Autodesk Fusion 360 part; units mm, degrees
(part 2 of 2)
sketch "Sketch23" plane through (0, 0, 0) normal (0, 0, 1) x (-1, 0, 0)
  circle A0 centre (51.1884, 99.1347) radius 1.85
  circle A1 centre (75.5913, 102.5343) radius 0.8
  circle A2 centre (-90.0969, -79.2783) radius 0.8
  circle A3 centre (90.1725, -79.2921) radius 0.8
  circle A4 centre (90.1026, 79.3599) radius 0.8
  circle A5 centre (51.1939, -99.1597) radius 1.85
  circle A6 centre (0.0682, 99.4831) radius 1.85
  circle A7 centre (-108.7523, -13.6846) radius 0.8
  circle A8 centre (-51.0571, 99.1371) radius 1.85
  circle A9 centre (75.6553, -102.4768) radius 0.8
  circle A10 centre (108.8477, -13.679) radius 0.8
  circle A11 centre (-89.9874, 79.369) radius 0.8
  circle A12 centre (-51.1366, -99.1566) radius 1.85
  circle A13 centre (108.8477, 13.668) radius 0.8
  circle A14 centre (-75.5979, -102.4631) radius 0.8
  circle A15 centre (-75.515, 102.4682) radius 0.8
  circle A16 centre (-108.7523, 13.7506) radius 0.8
  line L0 (-69.3323, -105.7468) -> (-36.906, -110.0169)
  line L1 (-36.906, -110.0169) -> (36.954, -110.0169)
  line L2 (36.954, -110.0169) -> (69.3862, -105.7589)
  arc A17 (75.995, -107.1982) -> (69.3862, -105.7589) centre (70.688, -115.6738) ccw
  line L3 (75.995, -107.1982) -> (91.7226, -117.0462)
  arc A18 (91.7226, -117.0462) -> (101.3705, -114.8282) centre (95.4376, -111.1132) ccw
  line L4 (101.3705, -114.8282) -> (101.7116, -114.2834)
  line L5 (101.7116, -114.2834) -> (70.2248, -94.5678)
  line L6 (70.2248, -94.5678) -> (80.686, -77.8607)
  line L7 (80.686, -77.8607) -> (112.1728, -97.5763)
  line L8 (112.1728, -97.5763) -> (112.5139, -97.0316)
  arc A19 (112.5139, -97.0316) -> (110.2959, -87.3838) centre (106.581, -93.3167) ccw
  line L9 (110.2959, -87.3838) -> (94.5669, -77.535)
  arc A20 (90.3869, -72.2209) -> (94.5669, -77.535) centre (99.874, -69.0595) ccw
  line L10 (90.3869, -72.2209) -> (80.0477, -41.1942)
  line L11 (80.0477, -41.1942) -> (105.2515, -19.8703)
  arc A21 (111.7105, -17.5046) -> (105.2515, -19.8703) centre (111.7105, -27.5046) ccw
  line L12 (111.7105, -17.5046) -> (130.0589, -17.5046)
  arc A22 (130.0589, -17.5046) -> (137.0576, -10.3672) centre (130.0589, -10.5046) ccw
  line L13 (137.0576, -10.3672) -> (137.0477, -9.8646)
  line L14 (137.0477, -9.8646) -> (100.0477, -9.8646)
  line L15 (100.0477, -9.8646) -> (100.0477, 9.8404)
  line L16 (100.0477, 9.8404) -> (137.0477, 9.8404)
  line L17 (137.0477, 9.8404) -> (137.0579, 10.3626)
  arc A23 (137.0579, 10.3626) -> (130.0593, 17.4996) centre (130.0593, 10.4996) ccw
  line L18 (130.0593, 17.4996) -> (111.707, 17.4996)
  arc A24 (105.2527, 19.8614) -> (111.707, 17.4996) centre (111.707, 27.4996) ccw
  line L19 (105.2527, 19.8614) -> (80.0477, 41.1594)
  line L20 (80.0477, 41.1594) -> (90.3683, 72.2128)
  arc A25 (94.551, 77.5346) -> (90.3683, 72.2128) centre (99.8579, 69.059) ccw
  line L21 (94.551, 77.5346) -> (110.2761, 87.3808)
  arc A26 (110.2761, 87.3808) -> (112.4942, 97.0286) centre (106.5612, 93.3137) ccw
  line L22 (112.4942, 97.0286) -> (112.1557, 97.5692)
  line L23 (112.1557, 97.5692) -> (80.6688, 77.8538)
  line L24 (80.6688, 77.8538) -> (70.2143, 94.5503)
  line L25 (70.2143, 94.5503) -> (101.7012, 114.2657)
  line L26 (101.7012, 114.2657) -> (101.3627, 114.8063)
  arc A27 (101.3627, 114.8063) -> (91.7149, 117.0244) centre (95.4298, 111.0915) ccw
  line L27 (91.7149, 117.0244) -> (75.9857, 107.1756)
  arc A28 (69.38, 105.7359) -> (75.9857, 107.1756) centre (70.6787, 115.6512) ccw
  line L28 (69.38, 105.7359) -> (36.954, 109.9831)
  line L29 (36.954, 109.9831) -> (-0.4655, 114.9106)
  line L30 (-0.4655, 114.9106) -> (-36.8155, 109.9831)
  line L31 (-36.8155, 109.9831) -> (-69.2461, 105.7456)
  arc A29 (-75.8525, 107.1881) -> (-69.2461, 105.7456) centre (-70.5417, 115.6613) ccw
  line L32 (-75.8525, 107.1881) -> (-91.5766, 117.0435)
  arc A30 (-91.5766, 117.0435) -> (-101.2254, 114.8298) centre (-95.2942, 111.1123) ccw
  line L33 (-101.2254, 114.8298) -> (-101.5653, 114.2875)
  line L34 (-101.5653, 114.2875) -> (-70.0873, 94.5579)
  line L35 (-70.0873, 94.5579) -> (-80.5522, 77.8615)
  line L36 (-80.5522, 77.8615) -> (-112.0302, 97.591)
  line L37 (-112.0302, 97.591) -> (-112.3701, 97.0487)
  arc A31 (-112.3701, 97.0487) -> (-110.1564, 87.3999) centre (-106.4389, 93.3312) ccw
  line L38 (-110.1564, 87.3999) -> (-94.4364, 77.547)
  arc A32 (-90.2557, 72.2221) -> (-94.4364, 77.547) centre (-99.7471, 69.0738) ccw
  line L39 (-90.2557, 72.2221) -> (-79.9523, 41.1594)
  line L40 (-79.9523, 41.1594) -> (-105.1606, 19.861)
  arc A33 (-111.6069, 17.4996) -> (-105.1606, 19.861) centre (-111.6145, 27.4996) ccw
  line L41 (-111.6069, 17.4996) -> (-130.1099, 17.4857)
  arc A34 (-130.1099, 17.4857) -> (-137.1046, 10.4595) centre (-130.1047, 10.4857) ccw
  line L42 (-137.1046, 10.4595) -> (-137.1023, 9.8404)
  line L43 (-137.1023, 9.8404) -> (-99.9523, 9.8404)
  line L44 (-99.9523, 9.8404) -> (-99.9523, -9.8646)
  line L45 (-99.9523, -9.8646) -> (-137.1023, -9.8646)
  line L46 (-137.1023, -9.8646) -> (-137.0948, -10.2221)
  arc A35 (-137.0948, -10.2221) -> (-130.1562, -17.0751) centre (-130.0963, -10.0753) ccw
  line L47 (-130.1562, -17.0751) -> (-111.5933, -17.2339)
  arc A36 (-105.1837, -19.63) -> (-111.5933, -17.2339) centre (-111.6789, -27.2335) ccw
  line L48 (-105.1837, -19.63) -> (-79.9523, -41.1835)
  line L49 (-79.9523, -41.1835) -> (-90.3067, -72.2075)
  arc A37 (-94.4901, -77.5202) -> (-90.3067, -72.2075) centre (-99.7924, -69.0416) ccw
  line L50 (-94.4901, -77.5202) -> (-110.2242, -87.3598)
  arc A38 (-110.2242, -87.3598) -> (-112.4476, -97.0064) centre (-106.5126, -93.2948) ccw
  line L51 (-112.4476, -97.0064) -> (-112.1082, -97.549)
  line L52 (-112.1082, -97.549) -> (-80.6103, -77.8512)
  line L53 (-80.6103, -77.8512) -> (-70.1622, -94.5583)
  line L54 (-70.1622, -94.5583) -> (-101.6601, -114.2561)
  line L55 (-101.6601, -114.2561) -> (-101.3208, -114.7987)
  arc A39 (-101.3208, -114.7987) -> (-91.6742, -117.0222) centre (-95.3858, -111.0872) ccw
  line L56 (-91.6742, -117.0222) -> (-75.9402, -107.1826)
  arc A40 (-69.3323, -105.7468) -> (-75.9402, -107.1826) centre (-70.6379, -115.6612) ccw
  line L57 (-0.4655, 114.9106) -> (0.024, -110.0169)
  line L58 (-99.9523, -0.0121) -> (100.0477, -0.0121)
  circle A41 centre (49.1247, -56.1029) radius 1.9
  circle A42 centre (49.1247, -56.1029) radius 4.9
  circle A43 centre (-48.989, 56.0983) radius 1.9
  circle A44 centre (-48.989, 56.0983) radius 4.9
  circle A45 centre (49.1041, 56.0966) radius 1.9
  circle A46 centre (49.1041, 56.0966) radius 4.9
  circle A47 centre (-49.0489, -56.0992) radius 1.9
  circle A48 centre (-49.0489, -56.0992) radius 4.9
  circle A49 centre (49.1247, -56.1029) radius 4.9
  circle A50 centre (-49.0489, -56.0992) radius 4.9
  circle A51 centre (-48.989, 56.0983) radius 4.9
  circle A52 centre (49.1041, 56.0966) radius 4.9
  dimension "d322" = 3.8
  dimension "d323" = 3
  dimension "d325" = 3.8
  dimension "d326" = 3
  dimension "d328" = 3.8
  dimension "d329" = 3
  dimension "d331" = 3.8
  dimension "d332" = 3
  constraint coincident L29.end L30.start
  constraint midpoint L1 L57.end
  constraint midpoint L44 L58.start
  constraint midpoint L15 L58.end
  constraint concentric A41 A49
  constraint concentric A47 A50
  constraint concentric A43 A51
  constraint concentric A45 A52
  measures "d322" diameter of A41
  measures "d325" diameter of A43
  measures "d328" diameter of A45
  measures "d331" diameter of A47
extrude "Extrude34" cut sketch "Sketch23" against normal blind 20 contours A41 | A43 | A45 | A47 bodies 1
sketch "Sketch24" plane through (0, 0, -7) normal (0, 0, -1) x (1, 0, 0)
  circle A0 centre (48.989, 56.0983) radius 1.9
  circle A1 centre (-49.1041, 56.0966) radius 1.9
  circle A2 centre (49.0489, -56.0992) radius 1.9
  circle A3 centre (-49.1247, -56.1029) radius 1.9
  circle A4 centre (-0.0425, -54.0357) radius 4.85
  circle A5 centre (-0.0682, 99.4831) radius 4.85
  line L0 (32.7504, -102.5169) -> (72.4523, -39.0315)
  line L1 (72.4523, -39.0315) -> (72.4523, 39.0033)
  line L2 (72.4523, 39.0033) -> (32.6649, 102.4831)
  line L3 (32.6649, 102.4831) -> (-0.0682, 107.4831)
  line L4 (-0.0682, 107.4831) -> (-32.8012, 102.4831)
  line L5 (-32.8012, 102.4831) -> (-72.5477, 39.0051)
  line L6 (-72.5477, 39.0051) -> (-72.5477, -39.0398)
  line L7 (-72.5477, -39.0398) -> (-32.8013, -102.5169)
  line L8 (-32.8013, -102.5169) -> (32.7504, -102.5169)
  circle A6 centre (-49.1247, -56.1029) radius 3.4
  circle A7 centre (49.0489, -56.0992) radius 3.4
  circle A8 centre (48.989, 56.0983) radius 3.4
  circle A9 centre (-49.1041, 56.0966) radius 3.4
  dimension "d335" = 6.8
  dimension "d336" = 6.8
  dimension "d337" = 6.8
  dimension "d338" = 6.8
  constraint concentric A3 A6
  constraint concentric A2 A7
  constraint concentric A0 A8
  constraint concentric A1 A9
  measures "d335" diameter of A6
  measures "d336" diameter of A7
  measures "d337" diameter of A8
  measures "d338" diameter of A9
extrude "Extrude35" cut sketch "Sketch24" against normal blind 2 contours A6 | A7 | A8 | A9 bodies 1
delete_face "DeleteFace2" 1 faces at (-0.4811, 54.8773, -2) on bodies 1
sketch "Sketch25" plane through (0, 0, 0) normal (0, 0, 1) x (-1, 0, 0)
  line L0 (-69.3323, -105.7468) -> (-36.906, -110.0169)
  line L1 (-36.906, -110.0169) -> (36.954, -110.0169)
  line L2 (36.954, -110.0169) -> (69.3862, -105.7589)
  arc A0 (75.995, -107.1982) -> (69.3862, -105.7589) centre (70.688, -115.6738) ccw
  line L3 (75.995, -107.1982) -> (91.7226, -117.0462)
  arc A1 (91.7226, -117.0462) -> (101.3705, -114.8282) centre (95.4376, -111.1132) ccw
  line L4 (101.3705, -114.8282) -> (101.7116, -114.2834)
  line L5 (101.7116, -114.2834) -> (70.2248, -94.5678)
  line L6 (70.2248, -94.5678) -> (80.686, -77.8607)
  line L7 (80.686, -77.8607) -> (112.1728, -97.5763)
  line L8 (112.1728, -97.5763) -> (112.5139, -97.0316)
  arc A2 (112.5139, -97.0316) -> (110.2959, -87.3838) centre (106.581, -93.3167) ccw
  line L9 (110.2959, -87.3838) -> (94.5669, -77.535)
  arc A3 (90.3869, -72.2209) -> (94.5669, -77.535) centre (99.874, -69.0595) ccw
  line L10 (90.3869, -72.2209) -> (80.0477, -41.1942)
  line L11 (80.0477, -41.1942) -> (105.2515, -19.8703)
  arc A4 (111.7105, -17.5046) -> (105.2515, -19.8703) centre (111.7105, -27.5046) ccw
  line L12 (111.7105, -17.5046) -> (130.0589, -17.5046)
  arc A5 (130.0589, -17.5046) -> (137.0576, -10.3672) centre (130.0589, -10.5046) ccw
  line L13 (137.0576, -10.3672) -> (137.0477, -9.8646)
  line L14 (137.0477, -9.8646) -> (100.0477, -9.8646)
  line L15 (100.0477, -9.8646) -> (100.0477, 9.8404)
  line L16 (100.0477, 9.8404) -> (137.0477, 9.8404)
  line L17 (137.0477, 9.8404) -> (137.0579, 10.3626)
  arc A6 (137.0579, 10.3626) -> (130.0593, 17.4996) centre (130.0593, 10.4996) ccw
  line L18 (130.0593, 17.4996) -> (111.707, 17.4996)
  arc A7 (105.2527, 19.8614) -> (111.707, 17.4996) centre (111.707, 27.4996) ccw
  line L19 (105.2527, 19.8614) -> (80.0477, 41.1594)
  line L20 (80.0477, 41.1594) -> (90.3683, 72.2128)
  arc A8 (94.551, 77.5346) -> (90.3683, 72.2128) centre (99.8579, 69.059) ccw
  line L21 (94.551, 77.5346) -> (110.2761, 87.3808)
  arc A9 (110.2761, 87.3808) -> (112.4942, 97.0286) centre (106.5612, 93.3137) ccw
  line L22 (112.4942, 97.0286) -> (112.1557, 97.5692)
  line L23 (112.1557, 97.5692) -> (80.6688, 77.8538)
  line L24 (80.6688, 77.8538) -> (70.2143, 94.5503)
  line L25 (70.2143, 94.5503) -> (101.7012, 114.2657)
  line L26 (101.7012, 114.2657) -> (101.3627, 114.8063)
  arc A10 (101.3627, 114.8063) -> (91.7149, 117.0244) centre (95.4298, 111.0915) ccw
  line L27 (91.7149, 117.0244) -> (75.9857, 107.1756)
  arc A11 (69.38, 105.7359) -> (75.9857, 107.1756) centre (70.6787, 115.6512) ccw
  line L28 (69.38, 105.7359) -> (36.954, 109.9831)
  line L29 (36.954, 109.9831) -> (-0.4655, 114.9106)
  line L30 (-0.4655, 114.9106) -> (-36.8155, 109.9831)
  line L31 (-36.8155, 109.9831) -> (-69.2461, 105.7456)
  arc A12 (-75.8525, 107.1881) -> (-69.2461, 105.7456) centre (-70.5417, 115.6613) ccw
  line L32 (-75.8525, 107.1881) -> (-91.5766, 117.0435)
  arc A13 (-91.5766, 117.0435) -> (-101.2254, 114.8298) centre (-95.2942, 111.1123) ccw
  line L33 (-101.2254, 114.8298) -> (-101.5653, 114.2875)
  line L34 (-101.5653, 114.2875) -> (-70.0873, 94.5579)
  line L35 (-70.0873, 94.5579) -> (-80.5522, 77.8615)
  line L36 (-80.5522, 77.8615) -> (-112.0302, 97.591)
  line L37 (-112.0302, 97.591) -> (-112.3701, 97.0487)
  arc A14 (-112.3701, 97.0487) -> (-110.1564, 87.3999) centre (-106.4389, 93.3312) ccw
  line L38 (-110.1564, 87.3999) -> (-94.4364, 77.547)
  arc A15 (-90.2557, 72.2221) -> (-94.4364, 77.547) centre (-99.7471, 69.0738) ccw
  line L39 (-90.2557, 72.2221) -> (-79.9523, 41.1594)
  line L40 (-79.9523, 41.1594) -> (-105.1606, 19.861)
  arc A16 (-111.6069, 17.4996) -> (-105.1606, 19.861) centre (-111.6145, 27.4996) ccw
  line L41 (-111.6069, 17.4996) -> (-130.1099, 17.4857)
  arc A17 (-130.1099, 17.4857) -> (-137.1046, 10.4595) centre (-130.1047, 10.4857) ccw
  line L42 (-137.1046, 10.4595) -> (-137.1023, 9.8404)
  line L43 (-137.1023, 9.8404) -> (-99.9523, 9.8404)
  line L44 (-99.9523, 9.8404) -> (-99.9523, -9.8646)
  line L45 (-99.9523, -9.8646) -> (-137.1023, -9.8646)
  line L46 (-137.1023, -9.8646) -> (-137.0948, -10.2221)
  arc A18 (-137.0948, -10.2221) -> (-130.1562, -17.0751) centre (-130.0963, -10.0753) ccw
  line L47 (-130.1562, -17.0751) -> (-111.5933, -17.2339)
  arc A19 (-105.1837, -19.63) -> (-111.5933, -17.2339) centre (-111.6789, -27.2335) ccw
  line L48 (-105.1837, -19.63) -> (-79.9523, -41.1835)
  line L49 (-79.9523, -41.1835) -> (-90.3067, -72.2075)
  arc A20 (-94.4901, -77.5202) -> (-90.3067, -72.2075) centre (-99.7924, -69.0416) ccw
  line L50 (-94.4901, -77.5202) -> (-110.2242, -87.3598)
  arc A21 (-110.2242, -87.3598) -> (-112.4476, -97.0064) centre (-106.5126, -93.2948) ccw
  line L51 (-112.4476, -97.0064) -> (-112.1082, -97.549)
  line L52 (-112.1082, -97.549) -> (-80.6103, -77.8512)
  line L53 (-80.6103, -77.8512) -> (-70.1622, -94.5583)
  line L54 (-70.1622, -94.5583) -> (-101.6601, -114.2561)
  line L55 (-101.6601, -114.2561) -> (-101.3208, -114.7987)
  arc A22 (-101.3208, -114.7987) -> (-91.6742, -117.0222) centre (-95.3858, -111.0872) ccw
  line L56 (-91.6742, -117.0222) -> (-75.9402, -107.1826)
  arc A23 (-69.3323, -105.7468) -> (-75.9402, -107.1826) centre (-70.6379, -115.6612) ccw
  circle A24 centre (-108.7523, 13.7506) radius 0.8
  circle A25 centre (-75.515, 102.4682) radius 0.8
  circle A26 centre (-75.5979, -102.4631) radius 0.8
  circle A27 centre (108.8477, 13.668) radius 0.8
  circle A28 centre (-51.1366, -99.1566) radius 1.85
  circle A29 centre (-89.9874, 79.369) radius 0.8
  circle A30 centre (108.8477, -13.679) radius 0.8
  circle A31 centre (75.6553, -102.4768) radius 0.8
  circle A32 centre (-51.0571, 99.1371) radius 1.85
  circle A33 centre (-108.7523, -13.6846) radius 0.8
  circle A34 centre (0.0682, 99.4831) radius 1.85
  circle A35 centre (51.1939, -99.1597) radius 1.85
  circle A36 centre (90.1026, 79.3599) radius 0.8
  circle A37 centre (90.1725, -79.2921) radius 0.8
  circle A38 centre (-90.0969, -79.2783) radius 0.8
  circle A39 centre (75.5913, 102.5343) radius 0.8
  circle A40 centre (51.1884, 99.1347) radius 1.85
  circle A41 centre (49.1247, -56.1029) radius 1.9
  circle A42 centre (-49.0489, -56.0992) radius 1.9
  circle A43 centre (49.1041, 56.0966) radius 1.9
  circle A44 centre (-48.989, 56.0983) radius 1.9
  circle A45 centre (0.0425, -54.0357) radius 1.85
  line L57 (-12.5, 5) -> (12.5, 5)
  line L58 (12.5, 5) -> (12.5, -5)
  line L59 (12.5, -5) -> (-12.5, -5)
  line L60 (-12.5, -5) -> (-12.5, 5)
  line L61 (-12.5, 5) -> (12.5, -5) construction
  line L62 (12.5, 5) -> (-12.5, -5) construction
  dimension "d341" = 25
  dimension "d342" = 10
  constraint horizontal L57
  constraint perpendicular L57 L58
  constraint parallel L57 L59
  constraint parallel L58 L60
  constraint coincident L61 origin
  constraint coincident L62 origin
  measures "d341" distance of L58.end L59.end
  measures "d342" distance of L57.end L58.end
extrude "Extrude36" cut sketch "Sketch25" against normal blind 40 contours L57 L58 L59 L60 bodies 1
chamfer "Chamfer10" distance 5 angle 45 4 edges at (0, 5, 0) (-12.5, 0, 0) (12.5, 0, 0) (0, -5, 0) on bodies 1
extrude "Extrude37" add 1 faces at (-52.5318, 1.6782, -7) along direction (0, 0, -1) blind 0.9 on bodies 1 bodies 1
sketch "Sketch26" plane through (0, 0, 0) normal (0, 0, 1) x (-1, 0, 0)
  circle A0 centre (0.0425, -54.0357) radius 1.85
  circle A1 centre (-48.989, 56.0983) radius 1.9
  circle A2 centre (49.1041, 56.0966) radius 1.9
  circle A3 centre (-49.0489, -56.0992) radius 1.9
  circle A4 centre (49.1247, -56.1029) radius 1.9
  circle A5 centre (51.1884, 99.1347) radius 1.85
  circle A6 centre (75.5913, 102.5343) radius 0.8
  circle A7 centre (-90.0969, -79.2783) radius 0.8
  circle A8 centre (90.1725, -79.2921) radius 0.8
  circle A9 centre (90.1026, 79.3599) radius 0.8
  circle A10 centre (51.1939, -99.1597) radius 1.85
  circle A11 centre (0.0682, 99.4831) radius 1.85
  circle A12 centre (-108.7523, -13.6846) radius 0.8
  circle A13 centre (-51.0571, 99.1371) radius 1.85
  circle A14 centre (75.6553, -102.4768) radius 0.8
  circle A15 centre (108.8477, -13.679) radius 0.8
  circle A16 centre (-89.9874, 79.369) radius 0.8
  circle A17 centre (-51.1366, -99.1566) radius 1.85
  circle A18 centre (108.8477, 13.668) radius 0.8
  circle A19 centre (-75.5979, -102.4631) radius 0.8
  circle A20 centre (-75.515, 102.4682) radius 0.8
  circle A21 centre (-108.7523, 13.7506) radius 0.8
  line L0 (-69.3323, -105.7468) -> (-36.906, -110.0169)
  line L1 (-36.906, -110.0169) -> (36.954, -110.0169)
  line L2 (36.954, -110.0169) -> (69.3862, -105.7589)
  arc A22 (75.995, -107.1982) -> (69.3862, -105.7589) centre (70.688, -115.6738) ccw
  line L3 (75.995, -107.1982) -> (91.7226, -117.0462)
  arc A23 (91.7226, -117.0462) -> (101.3705, -114.8282) centre (95.4376, -111.1132) ccw
  line L4 (101.3705, -114.8282) -> (101.7116, -114.2834)
  line L5 (101.7116, -114.2834) -> (70.2248, -94.5678)
  line L6 (70.2248, -94.5678) -> (80.686, -77.8607)
  line L7 (80.686, -77.8607) -> (112.1728, -97.5763)
  line L8 (112.1728, -97.5763) -> (112.5139, -97.0316)
  arc A24 (112.5139, -97.0316) -> (110.2959, -87.3838) centre (106.581, -93.3167) ccw
  line L9 (110.2959, -87.3838) -> (94.5669, -77.535)
  arc A25 (90.3869, -72.2209) -> (94.5669, -77.535) centre (99.874, -69.0595) ccw
  line L10 (90.3869, -72.2209) -> (80.0477, -41.1942)
  line L11 (80.0477, -41.1942) -> (105.2515, -19.8703)
  arc A26 (111.7105, -17.5046) -> (105.2515, -19.8703) centre (111.7105, -27.5046) ccw
  line L12 (111.7105, -17.5046) -> (130.0589, -17.5046)
  arc A27 (130.0589, -17.5046) -> (137.0576, -10.3672) centre (130.0589, -10.5046) ccw
  line L13 (137.0576, -10.3672) -> (137.0477, -9.8646)
  line L14 (137.0477, -9.8646) -> (100.0477, -9.8646)
  line L15 (100.0477, -9.8646) -> (100.0477, 9.8404)
  line L16 (100.0477, 9.8404) -> (137.0477, 9.8404)
  line L17 (137.0477, 9.8404) -> (137.0579, 10.3626)
  arc A28 (137.0579, 10.3626) -> (130.0593, 17.4996) centre (130.0593, 10.4996) ccw
  line L18 (130.0593, 17.4996) -> (111.707, 17.4996)
  arc A29 (105.2527, 19.8614) -> (111.707, 17.4996) centre (111.707, 27.4996) ccw
  line L19 (105.2527, 19.8614) -> (80.0477, 41.1594)
  line L20 (80.0477, 41.1594) -> (90.3683, 72.2128)
  arc A30 (94.551, 77.5346) -> (90.3683, 72.2128) centre (99.8579, 69.059) ccw
  line L21 (94.551, 77.5346) -> (110.2761, 87.3808)
  arc A31 (110.2761, 87.3808) -> (112.4942, 97.0286) centre (106.5612, 93.3137) ccw
  line L22 (112.4942, 97.0286) -> (112.1557, 97.5692)
  line L23 (112.1557, 97.5692) -> (80.6688, 77.8538)
  line L24 (80.6688, 77.8538) -> (70.2143, 94.5503)
  line L25 (70.2143, 94.5503) -> (101.7012, 114.2657)
  line L26 (101.7012, 114.2657) -> (101.3627, 114.8063)
  arc A32 (101.3627, 114.8063) -> (91.7149, 117.0244) centre (95.4298, 111.0915) ccw
  line L27 (91.7149, 117.0244) -> (75.9857, 107.1756)
  arc A33 (69.38, 105.7359) -> (75.9857, 107.1756) centre (70.6787, 115.6512) ccw
  line L28 (69.38, 105.7359) -> (36.954, 109.9831)
  line L29 (36.954, 109.9831) -> (-0.4655, 114.9106)
  line L30 (-0.4655, 114.9106) -> (-36.8155, 109.9831)
  line L31 (-36.8155, 109.9831) -> (-69.2461, 105.7456)
  arc A34 (-75.8525, 107.1881) -> (-69.2461, 105.7456) centre (-70.5417, 115.6613) ccw
  line L32 (-75.8525, 107.1881) -> (-91.5766, 117.0435)
  arc A35 (-91.5766, 117.0435) -> (-101.2254, 114.8298) centre (-95.2942, 111.1123) ccw
  line L33 (-101.2254, 114.8298) -> (-101.5653, 114.2875)
  line L34 (-101.5653, 114.2875) -> (-70.0873, 94.5579)
  line L35 (-70.0873, 94.5579) -> (-80.5522, 77.8615)
  line L36 (-80.5522, 77.8615) -> (-112.0302, 97.591)
  line L37 (-112.0302, 97.591) -> (-112.3701, 97.0487)
  arc A36 (-112.3701, 97.0487) -> (-110.1564, 87.3999) centre (-106.4389, 93.3312) ccw
  line L38 (-110.1564, 87.3999) -> (-94.4364, 77.547)
  arc A37 (-90.2557, 72.2221) -> (-94.4364, 77.547) centre (-99.7471, 69.0738) ccw
  line L39 (-90.2557, 72.2221) -> (-79.9523, 41.1594)
  line L40 (-79.9523, 41.1594) -> (-105.1606, 19.861)
  arc A38 (-111.6069, 17.4996) -> (-105.1606, 19.861) centre (-111.6145, 27.4996) ccw
  line L41 (-111.6069, 17.4996) -> (-130.1099, 17.4857)
  arc A39 (-130.1099, 17.4857) -> (-137.1046, 10.4595) centre (-130.1047, 10.4857) ccw
  line L42 (-137.1046, 10.4595) -> (-137.1023, 9.8404)
  line L43 (-137.1023, 9.8404) -> (-99.9523, 9.8404)
  line L44 (-99.9523, 9.8404) -> (-99.9523, -9.8646)
  line L45 (-99.9523, -9.8646) -> (-137.1023, -9.8646)
  line L46 (-137.1023, -9.8646) -> (-137.0948, -10.2221)
  arc A40 (-137.0948, -10.2221) -> (-130.1562, -17.0751) centre (-130.0963, -10.0753) ccw
  line L47 (-130.1562, -17.0751) -> (-111.5933, -17.2339)
  arc A41 (-105.1837, -19.63) -> (-111.5933, -17.2339) centre (-111.6789, -27.2335) ccw
  line L48 (-105.1837, -19.63) -> (-79.9523, -41.1835)
  line L49 (-79.9523, -41.1835) -> (-90.3067, -72.2075)
  arc A42 (-94.4901, -77.5202) -> (-90.3067, -72.2075) centre (-99.7924, -69.0416) ccw
  line L50 (-94.4901, -77.5202) -> (-110.2242, -87.3598)
  arc A43 (-110.2242, -87.3598) -> (-112.4476, -97.0064) centre (-106.5126, -93.2948) ccw
  line L51 (-112.4476, -97.0064) -> (-112.1082, -97.549)
  line L52 (-112.1082, -97.549) -> (-80.6103, -77.8512)
  line L53 (-80.6103, -77.8512) -> (-70.1622, -94.5583)
  line L54 (-70.1622, -94.5583) -> (-101.6601, -114.2561)
  line L55 (-101.6601, -114.2561) -> (-101.3208, -114.7987)
  arc A44 (-101.3208, -114.7987) -> (-91.6742, -117.0222) centre (-95.3858, -111.0872) ccw
  line L56 (-91.6742, -117.0222) -> (-75.9402, -107.1826)
  arc A45 (-69.3323, -105.7468) -> (-75.9402, -107.1826) centre (-70.6379, -115.6612) ccw
  line L57 (-17.5, 10) -> (17.5, 10)
  line L58 (17.5, 10) -> (17.5, -10)
  line L59 (17.5, -10) -> (-17.5, -10)
  line L60 (-17.5, -10) -> (-17.5, 10)
  line L61 (-80.6103, -77.8512) -> (-88.1607, -65.7777)
  line L62 (-88.1607, -65.7777) -> (-79.9523, -41.1835)
  line L63 (-99.9523, -9.8646) -> (-99.9523, -24.0989)
  line L64 (-99.9523, -24.0989) -> (-79.9523, -41.1835)
  line L65 (-99.9523, 9.8404) -> (-99.9523, 24.2615)
  line L66 (-99.9523, 24.2615) -> (-79.9523, 41.1594)
  line L67 (-80.5522, 77.8615) -> (-88.1208, 65.7859)
  line L68 (-88.1208, 65.7859) -> (-79.9523, 41.1594)
  line L69 (-80.5522, 77.8615) -> (-62.5247, 106.6238)
  line L70 (-99.9523, -9.8646) -> (-99.9523, 9.8404)
  line L71 (-80.6103, -77.8512) -> (-62.6118, -106.6318)
  line L72 (-62.5247, 106.6238) -> (-0.4655, 114.9106)
  line L73 (70.2143, 94.5503) -> (62.6593, 106.6162)
  line L74 (62.6593, 106.6162) -> (-1.2851, 115.0366)
  line L75 (70.2143, 94.5503) -> (88.2298, 65.7783)
  line L76 (88.2298, 65.7783) -> (80.0477, 41.1594)
  line L77 (100.0477, 9.8404) -> (100.0477, 24.2596)
  line L78 (100.0477, 24.2596) -> (80.0477, 41.1594)
  line L79 (100.0477, 9.8404) -> (100.0477, -24.273)
  line L80 (100.0477, -24.273) -> (80.0477, -41.1942)
  line L81 (80.686, -77.8607) -> (88.244, -65.7903)
  line L82 (80.0477, -41.1942) -> (88.244, -65.7903)
  line L83 (80.686, -77.8607) -> (62.6649, -106.6413)
  line L84 (62.6649, -106.6413) -> (36.954, -110.0169)
  line L85 (36.954, -110.0169) -> (-36.906, -110.0169)
  line L86 (-62.6118, -106.6318) -> (-36.906, -110.0169)
  line L87 (-59.5353, 101.9786) -> (-0.3928, 109.8759)
  line L88 (-76.3156, 75.2061) -> (-59.5353, 101.9786)
  line L89 (-76.3156, 75.2061) -> (-82.6338, 65.1254)
  line L90 (-82.6338, 65.1254) -> (-74.1416, 39.5231)
  line L91 (-94.9523, 21.9403) -> (-74.1416, 39.5231)
  line L92 (-94.9523, 9.8404) -> (-94.9523, 21.9403)
  line L93 (-94.9523, -9.8646) -> (-94.9523, 9.8404)
  line L94 (-94.9523, -9.8646) -> (-94.9523, -21.7941)
  line L95 (-94.9523, -21.7941) -> (-74.1427, -39.5703)
  line L96 (-82.6717, -65.1249) -> (-74.1427, -39.5703)
  line L97 (-76.371, -75.2) -> (-82.6717, -65.1249)
  line L98 (-76.371, -75.2) -> (-59.6222, -101.9823)
  line L99 (-59.6222, -101.9823) -> (-36.5782, -105.0169)
  line L100 (36.6272, -105.0169) -> (-36.5782, -105.0169)
  line L101 (59.6777, -101.9906) -> (36.6272, -105.0169)
  line L102 (76.4482, -75.2072) -> (59.6777, -101.9906)
  line L103 (76.4482, -75.2072) -> (82.7552, -65.1347)
  line L104 (74.234, -39.5635) -> (82.7552, -65.1347)
  line L105 (95.0477, -21.9539) -> (74.234, -39.5635)
  line L106 (95.0477, 9.8404) -> (95.0477, -21.9539)
  line L107 (95.0477, 9.8404) -> (95.0477, 21.9385)
  line L108 (95.0477, 21.9385) -> (74.2355, 39.5247)
  line L109 (82.7423, 65.1206) -> (74.2355, 39.5247)
  line L110 (65.9765, 91.8968) -> (82.7423, 65.1206)
  line L111 (65.9765, 91.8968) -> (59.6714, 101.9665)
  line L112 (59.6714, 101.9665) -> (-0.3928, 109.8759)
  circle A46 centre (74.7552, -65.1347) radius 4
  circle A47 centre (74.7552, -65.1347) radius 1.9
  line L113 (-82.6717, -65.1249) -> (-74.6717, -65.1249)
  circle A48 centre (-74.6717, -65.1249) radius 4
  circle A49 centre (-74.6717, -65.1249) radius 1.9
  line L114 (82.7423, 65.1206) -> (74.7423, 65.1206)
  circle A50 centre (74.7423, 65.1206) radius 4
  circle A51 centre (74.7423, 65.1206) radius 1.9
  line L115 (-82.6338, 65.1254) -> (-74.6338, 65.1254)
  circle A52 centre (-74.6338, 65.1254) radius 4
  circle A53 centre (-74.6338, 65.1254) radius 1.9
  dimension "d348" = 5
  dimension "d351" = 8
  dimension "d352" = 8
  dimension "d353" = 3.8
  dimension "d354" = 8
  dimension "d355" = 8
  dimension "d356" = 3.8
  dimension "d357" = 8
  dimension "d358" = 8
  dimension "d359" = 3.8
  dimension "d360" = 8
  dimension "d361" = 8
  dimension "d362" = 3.8
  constraint coincident L52.end L53.start
  constraint coincident L49 L61.end
  constraint perpendicular L52 L61
  constraint coincident L48.end L49.start
  constraint coincident L44.end L45.start
  constraint coincident L48 L63.end
  constraint perpendicular L45 L63
  constraint coincident L43.end L44.start
  constraint coincident L40 L65.end
  constraint perpendicular L43 L65
  constraint coincident L39.end L40.start
  constraint coincident L35.end L36.start
  constraint coincident L39 L67.end
  constraint perpendicular L36 L67
  constraint coincident L31 L69.end
  constraint perpendicular L34 L69
  constraint coincident L0 L71.end
  constraint perpendicular L54 L71
  constraint coincident L29.end L30.start
  constraint coincident L24.end L25.start
  constraint coincident L28 L73.end
  constraint perpendicular L25 L73
  constraint parallel L29 L74
  constraint coincident L20 L75.end
  constraint perpendicular L23 L75
  constraint coincident L19.end L20.start
  constraint coincident L15.end L16.start
  constraint coincident L19 L77.end
  constraint perpendicular L16 L77
  constraint coincident L11 L79.end
  constraint parallel L15 L79
  constraint coincident L10.end L11.start
  constraint coincident L6.end L7.start
  constraint coincident L10 L81.end
  constraint perpendicular L7 L81
  constraint coincident L2 L83.end
  constraint perpendicular L5 L83
  constraint coincident L1.end L2.start
  constraint coincident L0.end L1.start
  constraint concentric A46 A47
  constraint horizontal L113
  constraint coincident L113.end A48.centre
  constraint concentric A48 A49
  constraint horizontal L114
  constraint coincident L114.end A50.centre
  constraint concentric A50 A51
  constraint horizontal L115
  constraint coincident L115.end A52.centre
  constraint concentric A52 A53
  measures "d351" distance of L103.end A46.centre
  measures "d352" diameter of A46
  measures "d353" diameter of A47
  measures "d354" distance of L96.start L113.end
  measures "d355" diameter of A48
  measures "d356" diameter of A49
  measures "d357" distance of L109.start L114.end
  measures "d358" diameter of A50
  measures "d359" diameter of A51
  measures "d360" distance of L89.end L115.end
  measures "d361" diameter of A52
  measures "d362" diameter of A53
extrude "Extrude38" add sketch "Sketch26" along normal blind 18 contours L0 L1 L2 L6 L10 L11 L15 L19 L20 L24 L28 L29 L30 L31 L35 L39 L40 L44 L48 L49 L53 L61 L62 L63 L64 L65 L66 L67 L68 L69 L70 L71 L73 L75 L76 L77 L78 L79 L80 L81 L82 L83 L84 L85 L86 bodies 1
extrude "Extrude39" add sketch "Sketch26" along normal blind 18 contours A46 | A48 | A50 | A52 bodies 1
delete_face "DeleteFace3" 1 faces at (-4.9122, -99.7248, -8.5667) on bodies 1
delete_face "DeleteFace4" 1 faces at (-4.8864, 53.7939, -8.5667) on bodies 1

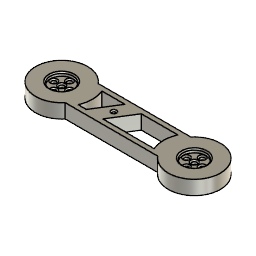
design "FemurHornSideV2"
part number: 2025-10-31-15-56-20-777
Autodesk Fusion 360 part; units mm, degrees
sketch "Sketch1" plane through (0, 0, 0) normal (0, 0, 1) x (1, 0, 0)
  line L0 (39.0943, -14) -> (-39.0943, -14)
  line L1 (-39.0943, 14) -> (39.0943, 14)
  line L2 (35.2103, -7.0421) -> (-35.2103, 7.0421) construction
  line L3 (-35.2103, -7.0421) -> (35.2103, 7.0421) construction
  circle A0 centre (56, 0) radius 21.95
  circle A1 centre (-56, 0) radius 21.95
  circle A2 centre (56, 0) radius 13
  line L4 (-39.0943, -14) -> (-24.0943, -14)
  line L5 (-21.5994, -10) -> (-9.1249, 10)
  line L6 (-6.6301, 14) -> (0.1699, 14)
  line L7 (-2.3249, 10) -> (-14.7994, -10)
  line L8 (-24.0943, -14) -> (-17.2943, -14)
  line L9 (1.2108, 10) -> (-11.2637, -10)
  line L10 (-25.1351, -10) -> (-12.6607, 10)
  line L11 (-24.0943, -14) -> (-17.2943, -14)
  line L12 (-2.3249, 10) -> (-14.7994, -10)
  line L13 (-6.6301, 14) -> (0.1699, 14)
  line L14 (-21.5994, -10) -> (-9.1249, 10)
  arc A3 (-32.0542, -10) -> (-32.0542, 10) centre (-56, 0) ccw
  line L15 (32.0542, -10) -> (-32.0542, -10)
  line L16 (-32.0542, 10) -> (32.0542, 10)
  arc A4 (32.0542, 10) -> (32.0542, -10) centre (56, 0) ccw
  circle A5 centre (-56, 0) radius 2
  circle A6 centre (-56, 0) radius 19.95
  circle A7 centre (-56, 0) radius 13.34
  circle A8 centre (-56, 0) radius 9.65
  circle A9 centre (-56, 6.65) radius 3
  circle A10 centre (-56, 6.65) radius 1.9
  circle A11 centre (-62.65, 0) radius 1.9
  circle A12 centre (-56, -6.65) radius 1.9
  circle A13 centre (-49.35, 0) radius 1.9
  circle A14 centre (56, 0) radius 2
  circle A15 centre (56, 0) radius 19.95
  circle A16 centre (56, 0) radius 9.65
  circle A17 centre (49.35, 0.0073) radius 3
  circle A18 centre (49.35, 0.0073) radius 1.9
  circle A19 centre (55.9927, -6.65) radius 1.9
  circle A20 centre (62.65, -0.0073) radius 1.9
  circle A21 centre (56.0073, 6.65) radius 1.9
  line L17 (-9.1249, 10) -> (-2.3249, 10)
  dimension "d11" = 26
  dimension "d15" = 15
  dimension "d16" = 33
  dimension "d32" = 4
  dimension "d43" = 3.8
  dimension "d45" = 360
  dimension "d51" = 4
  dimension "d53" = 19.3
  dimension "d55" = 6
  dimension "d56" = 3.8
  dimension "d58" = 360
  dimension "d95" = 6.8
  dimension "d96" = 78.1886
  dimension "d97" = 39.9
  dimension "d98" = 43.9
  dimension "d99" = 64.1084
  constraint horizontal L0
  constraint parallel L0 L1
  constraint coincident L2 origin
  constraint coincident L3 origin
  constraint coincident A1 L1.start
  constraint coincident A1 L0.end
  constraint coincident A1 L3.start
  constraint coincident A1 L2.end
  constraint coincident A0 L1.end
  constraint coincident A0 L0.start
  constraint coincident A0 L3.end
  constraint coincident A0 L2.start
  constraint parallel L0 L4
  constraint coincident L1 L6.start
  constraint parallel L1 L6
  constraint coincident L0 L8.end
  constraint concentric A1 A3
  constraint coincident L15 L10.start
  constraint coincident L15 L7.end
  constraint coincident L15 L5.start
  constraint coincident L15 L9.end
  constraint concentric A0 A4
  constraint coincident L16 L10.end
  constraint coincident L16 L5.end
  constraint coincident L16 L7.start
  constraint coincident L16 L9.start
  constraint concentric A3 A6
  constraint concentric A5 A7
  constraint concentric A6 A8
  constraint concentric A9 A10
  constraint concentric A2 A14
  constraint concentric A0 A15
  constraint concentric A0 A16
  constraint concentric A17 A18
  measures "d11" diameter of A2
  measures "d15" distance of L0.end L4.end
  measures "d16" distance of L4.end L6.start
  measures "d32" diameter of A5
  measures "d43" diameter of A10
  measures "d51" diameter of A14
  measures "d53" diameter of A16
  measures "d55" diameter of A17
  measures "d56" diameter of A18
  measures "d95" distance of L5.end L7.start
  measures "d96" distance of L1.start L1.end
  measures "d97" diameter of A15
  measures "d98" diameter of A0
  measures "d99" distance of A3.end L16.end
extrude "Extrude1" add sketch "Sketch1" along normal blind 12 contours L0 L1 A0 A1 L4 L6 L8 L11 L13 | A0 | A1 | A2 | L5 L10 L14 L15 L16 | L7 L9 L12 L15 L16 | A5 | A6 | A7 | A9 | A8 | A10 | A11 | A12 | A13 | A14 | A15 | A17 | A16 | A18 | A19 | A20 | A21
extrude "Extrude4" cut sketch "Sketch1" along normal blind 17 contours A5
extrude "Extrude5" cut sketch "Sketch1" along normal blind 17 contours A10 | A11 | A12 | A13
extrude "Extrude7" cut sketch "Sketch1" along normal blind 12 contours A14 | A18 | A19 | A20 | A21
sketch "Sketch8" plane through (0, 0, 0) normal (0, 0, -1) x (1, 0, 0)
  circle A0 centre (55.9927, 6.65) radius 1.9
  circle A1 centre (49.35, -0.0073) radius 1.9
  circle A2 centre (62.65, 0.0073) radius 1.9
  circle A3 centre (56, 0) radius 2
  circle A4 centre (56.0073, -6.65) radius 1.9
  circle A5 centre (-56, 6.65) radius 1.9
  circle A6 centre (-62.65, 0) radius 1.9
  circle A7 centre (-49.35, 0) radius 1.9
  circle A8 centre (-56, -6.65) radius 1.9
  circle A9 centre (-56, 0) radius 2
  line L0 (-25.1351, 10) -> (-12.6607, -10)
  line L1 (-12.6607, -10) -> (-32.0542, -10)
  arc A10 (-32.0542, -10) -> (-32.0542, 10) centre (-56, 0) ccw
  line L2 (-32.0542, 10) -> (-25.1351, 10)
  line L3 (-21.5994, 10) -> (-14.7994, 10)
  line L4 (-14.7994, 10) -> (-2.3249, -10)
  line L5 (-2.3249, -10) -> (-9.1249, -10)
  line L6 (-9.1249, -10) -> (-21.5994, 10)
  line L7 (1.2108, -10) -> (-11.2637, 10)
  line L8 (-11.2637, 10) -> (32.0542, 10)
  arc A11 (32.0542, 10) -> (32.0542, -10) centre (56, 0) ccw
  line L9 (32.0542, -10) -> (1.2108, -10)
  arc A12 (-39.0943, 14) -> (-39.0943, -14) centre (-56, 0) ccw
  line L10 (-39.0943, -14) -> (39.0943, -14)
  arc A13 (39.0943, -14) -> (39.0943, 14) centre (56, 0) ccw
  line L11 (39.0943, 14) -> (-39.0943, 14)
  circle A14 centre (-56, 0) radius 10
  circle A15 centre (56, 0) radius 10
  dimension "d81" = 20
  dimension "d82" = 20
  constraint concentric A9 A14
  constraint concentric A3 A15
  measures "d81" diameter of A14
  measures "d82" diameter of A15
extrude "Extrude13" cut sketch "Sketch8" against normal blind 6 contours A14 | A15
sketch "Sketch9" plane through (0, 0, 12) normal (0, 0, 1) x (-1, 0, 0)
  line L0 (12.6607, -10) -> (25.1351, 10)
  line L1 (25.1351, 10) -> (32.0542, 10)
  arc A0 (32.0542, 10) -> (32.0542, -10) centre (56, 0) ccw
  line L2 (32.0542, -10) -> (12.6607, -10)
  line L3 (14.7994, 10) -> (21.5994, 10)
  line L4 (21.5994, 10) -> (9.1249, -10)
  line L5 (9.1249, -10) -> (2.3249, -10)
  line L6 (2.3249, -10) -> (14.7994, 10)
  line L7 (11.2637, 10) -> (-1.2108, -10)
  line L8 (-1.2108, -10) -> (-32.0542, -10)
  arc A1 (-32.0542, -10) -> (-32.0542, 10) centre (-56, 0) ccw
  line L9 (-32.0542, 10) -> (11.2637, 10)
  arc A2 (39.0943, -14) -> (39.0943, 14) centre (56, 0) ccw
  line L10 (39.0943, 14) -> (-39.0943, 14)
  arc A3 (-39.0943, 14) -> (-39.0943, -14) centre (-56, 0) ccw
  line L11 (-39.0943, -14) -> (39.0943, -14)
  line L12 (21.445, 9.2275) -> (8.9704, -10.7727)
  line L13 (8.9704, -10.7727) -> (2.17, -10.7727)
  line L14 (21.445, 9.2275) -> (14.645, 9.2275)
  line L15 (14.645, 9.2275) -> (2.17, -10.7727)
  circle A4 centre (-55.9927, 6.65) radius 1.9
  circle A5 centre (-49.35, -0.0073) radius 1.9
  circle A6 centre (-62.65, 0.0073) radius 1.9
  circle A7 centre (-56, 0) radius 2
  circle A8 centre (-56.0073, -6.65) radius 1.9
  circle A9 centre (56, 6.65) radius 1.9
  circle A10 centre (62.65, 0) radius 1.9
  circle A11 centre (49.35, 0) radius 1.9
  circle A12 centre (56, -6.65) radius 1.9
  circle A13 centre (56, 0) radius 2
  constraint parallel L4 L12
  constraint parallel L5 L13
  constraint parallel L3 L14
extrude "Extrude14" add sketch "Sketch9" against normal blind 7 contours L3 L4 L5 L6 L14 L15 | L4 L5 L14 L15
sketch "Sketch10" plane through (0, 0, 12) normal (0, 0, 1) x (-1, 0, 0)
  line L0 (12.6607, -10) -> (25.1351, 10)
  line L1 (25.1351, 10) -> (32.0542, 10)
  arc A0 (32.0542, 10) -> (32.0542, -10) centre (56, 0) ccw
  line L2 (32.0542, -10) -> (12.6607, -10)
  line L3 (11.2637, 10) -> (-1.2108, -10)
  line L4 (-1.2108, -10) -> (-32.0542, -10)
  arc A1 (-32.0542, -10) -> (-32.0542, 10) centre (-56, 0) ccw
  line L5 (-32.0542, 10) -> (11.2637, 10)
  arc A2 (39.0943, -14) -> (39.0943, 14) centre (56, 0) ccw
  line L6 (39.0943, 14) -> (-39.0943, 14)
  arc A3 (-39.0943, 14) -> (-39.0943, -14) centre (-56, 0) ccw
  line L7 (-39.0943, -14) -> (39.0943, -14)
  circle A4 centre (-56, 0) radius 10
  circle A5 centre (56, 0) radius 10
  circle A6 centre (56, 0) radius 9.65
  circle A7 centre (-56, 0) radius 9.65
  circle A8 centre (-55.9927, 6.65) radius 1.9
  circle A9 centre (-49.35, -0.0073) radius 1.9
  circle A10 centre (-62.65, 0.0073) radius 1.9
  circle A11 centre (-56, 0) radius 2
  circle A12 centre (-56.0073, -6.65) radius 1.9
  circle A13 centre (56, 6.65) radius 1.9
  circle A14 centre (62.65, 0) radius 1.9
  circle A15 centre (49.35, 0) radius 1.9
  circle A16 centre (56, -6.65) radius 1.9
  circle A17 centre (56, 0) radius 2
  dimension "d88" = 20
  dimension "d89" = 20
  constraint concentric A1 A4
  measures "d88" diameter of A4
  measures "d89" diameter of A5
extrude "Extrude15" cut sketch "Sketch10" against normal blind 3 contours A6 | A7 | A8 | A9 | A10 | A11 | A12 | A13 | A14 | A15 | A16 | A17
sketch "Sketch11" plane through (0, 0, 12) normal (0, 0, 1) x (-1, 0, 0)
  line L0 (12.6607, -10) -> (25.1351, 10)
  line L1 (25.1351, 10) -> (32.0542, 10)
  arc A0 (32.0542, 10) -> (32.0542, -10) centre (56, 0) ccw
  line L2 (32.0542, -10) -> (12.6607, -10)
  line L3 (11.2637, 10) -> (-1.2108, -10)
  line L4 (-1.2108, -10) -> (-32.0542, -10)
  arc A1 (-32.0542, -10) -> (-32.0542, 10) centre (-56, 0) ccw
  line L5 (-32.0542, 10) -> (11.2637, 10)
  arc A2 (39.0943, -14) -> (39.0943, 14) centre (56, 0) ccw
  line L6 (39.0943, 14) -> (-39.0943, 14)
  arc A3 (-39.0943, 14) -> (-39.0943, -14) centre (-56, 0) ccw
  line L7 (-39.0943, -14) -> (39.0943, -14)
  circle A4 centre (11.9622, 0) radius 1.25
  circle A5 centre (56, 0) radius 9.65
  circle A6 centre (-56, 0) radius 9.65
  dimension "d92" = 2.5
  measures "d92" diameter of A4
extrude "Extrude16" cut sketch "Sketch11" against normal blind 19 contours A4
chamfer "Chamfer4" distance 1 angle 45 15 edges at (-65.3233, -3.6162, 0) (46.6767, -3.6162, 0) (47.5786, -0.6797, 9) (54.1353, -0.7232, 9) (54.2212, -7.3371, 9) (60.8786, -0.6944, 9) (54.2359, 5.9629, 9) (64.997, -3.4896, 12) (-47.003, -3.4896, 12) (-64.4214, -0.6871, 9) (-57.8647, -0.7232, 9) (-57.7714, 5.9629, 9) (-51.1214, -0.6871, 9) (-57.7714, -7.3371, 9) (-10.7968, -0.452, 12)
